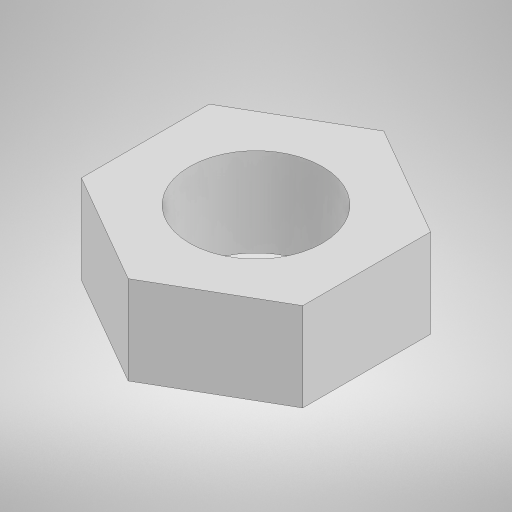
# Autodesk Inventor part: tuerca
Saved by Autodesk Inventor 2023 (Build 270158000, 158)
## iProperties
Created: 2023-05-19
Part Number: tuerca
Material: Genérico
Document SubType Name: Modeling
Designer: brand
Density: 1 g/cm^3
Appearance: Valor por defecto
Author: brand
Autodesk Inventor part; units mm, degrees
ref_plane "YZ Plane" through (0, 0, 0) normal (1, 0, 0) x (0, 1, 0)
ref_plane "XZ Plane" through (0, 0, 0) normal (0, 1, 0) x (-1, 0, 0)
ref_plane "XY Plane" through (0, 0, 0) normal (0, 0, 1) x (1, 0, 0)
sketch "Boceto1" plane through (0, 0, 0) normal (0, 1, 0) x (-1, 0, 0)
  line L0 (5, 2.8868) -> (5, -2.8868)
  line L1 (5, -2.8868) -> (0, -5.7735)
  line L2 (0, -5.7735) -> (-5, -2.8868)
  line L3 (-5, -2.8868) -> (-5, 2.8868)
  line L4 (-5, 2.8868) -> (0, 5.7735)
  line L5 (0, 5.7735) -> (5, 2.8868)
  circle A0 centre (0, 0) radius 3
  point P0 (5, 0)
  dimension "d0" = 10
  dimension "d1" = 10
  dimension "d2" = 10
  dimension "d3" = 120
  dimension "d4" = 120
  dimension "d5" = 6
  constraints: 12 end point, 3 parallel, 1 centre point, 1 coincident, 1 equal length, 1 horizontal alignment, 1 midpoint, 1 vertical, 1 vertical alignment
  measures "d0" distance between parallel lines of L3 L0
  measures "d1" distance between parallel lines of L4 L1
  measures "d2" distance between parallel lines of L2 L5
  measures "d3" angle of L5 L0
  measures "d4" angle of L2 L1
  measures "d5" diameter of A0
extrude "Extrusión1" add sketch "Boceto1" along normal blind 4
equation "\"d1\" = d0"
equation "\"d2\" = d0"
equation "\"d4\" = d3"
